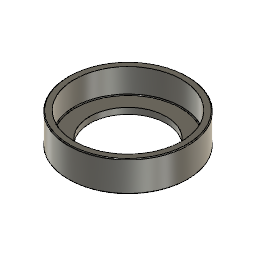
astra-sv-solar-filter-body (Autodesk Fusion 360 design; units mm, degrees)
part number: 2026-01-25-13-45-08-993
Autodesk Fusion 360 part; units mm, degrees
sketch "Sketch2" plane through (0, 0, 0) normal (0, 1, 0) x (1, 0, 0)
  line L0 (-35, -20) -> (-38.5, -20)
  line L1 (-39, -19.5) -> (-39, -0.5)
  line L2 (-38.5, 0) -> (-35, 0)
  line L3 (-35, 0) -> (-25, 0)
  line L4 (-25, 0) -> (-25, -4)
  line L5 (-25, -4) -> (-34.5, -4)
  line L6 (-35, -20) -> (-35, -4.5)
  arc A0 (-34.5, -4) -> (-35, -4.5) centre (-34.5, -4.5) ccw
  arc A1 (-38.5, 0) -> (-39, -0.5) centre (-38.5, -0.5) ccw
  arc A2 (-39, -19.5) -> (-38.5, -20) centre (-38.5, -19.5) ccw
  point P0 (-39, -20)
  point P1 (-39, 0)
  point P2 (-35, -4)
  dimension "d1" = 4
  dimension "d2" = 20
  dimension "d3" = 4
  dimension "d4" = 10
  dimension "d5" = 0.5
  dimension "d6" = 0.5
  dimension "d7" = 0.5
  constraint perpendicular L0 L1
  constraint perpendicular L3 L4
  constraint perpendicular L0 L6
  constraint coincident P2 L5
  constraint coincident P2 L6
  constraint tangent L5 A0
  constraint tangent L6 A0
  constraint coincident P1 L1
  constraint coincident P1 L2
  constraint tangent L1 A1
  constraint tangent L2 A1
  constraint coincident P0 L0
  constraint coincident P0 L1
  constraint tangent L0 A2
  constraint tangent L1 A2
  measures "d1" distance of L0.start P0
  measures "d2" distance of P0 P1
  measures "d3" distance of L3.end L4.end
  measures "d4" distance of L4.end P2
  measures "d5" radius of A0
  measures "d6" radius of A1
  measures "d7" radius of A2
revolve "Revolve1" add sketch "Sketch2" angle 360 about axis through (0, 0, 1.75) along (0, 0, 1)
named bodies: "astra-sv-solar-filter-body"
